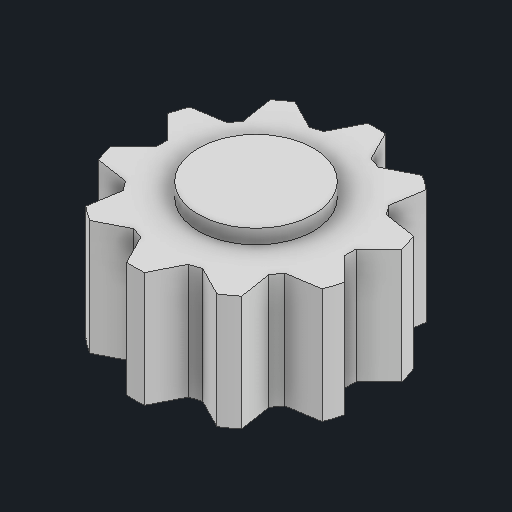
# Autodesk Inventor part: motor_gear
Saved by Autodesk Inventor 2026.1 (Build 301233020, 233B)
## iProperties
Created: 2025-11-26
Part Number: motor_gear
Material: Generico
Document SubType Name: Modeling
Designer: maxbu
Density: 1 g/cm^3
Appearance: Default
Author: maxbu
Autodesk Inventor part; units mm, degrees
ref_plane "YZ Plane" through (0, 0, 0) normal (1, 0, 0) x (0, 1, 0)
ref_plane "XZ Plane" through (0, 0, 0) normal (0, 1, 0) x (-1, 0, 0)
ref_plane "XY Plane" through (0, 0, 0) normal (0, 0, 1) x (1, 0, 0)
sketch "Sketch6" plane through (0, 0, 0) normal (0, 1, 0) x (-1, 0, 0)
  circle A0 centre (0, 0) radius 4.2
  dimension "d37" = 8.4
  constraints: 1 centre point, 1 coincident
  measures "d37" diameter of A0
extrude "Extrusion5" add sketch "Sketch6" along normal blind 4
sketch "Sketch7" plane through (0, 0, 0) normal (0, 1, 0) x (-1, 0, 0)
  circle A0 centre (0, 0) radius 4.2 projected
  line L0 (-5.88, 0) -> (5.88, 0) projected
  line L1 (4.0792, 1) -> (3.2792, 0.2)
  line L2 (3.2792, -0.2) -> (4.0792, -1)
  line L3 (3.2792, 0.2) -> (3.2792, -0.2)
  dimension "d44" = 45
  dimension "d45" = 1
  dimension "d46" = 0.8
  dimension "d47" = 0.4
  constraints: 6 end point, 2 point on circle, 1 vertical, 1 other
  measures "d44" angle of L0 L1
  measures "d45" distance from line of L2.end L0
  measures "d46" horizontal distance of L2.end L2.start
  measures "d47" distance of L2.start L1.end
extrude "Extrusion6" cut sketch "Sketch7" along normal through all contours L0 L3 L1 A0 | A0 L2 L3 L0 picked at (3.8349, 0.6234) picked at (3.8349, -0.6234)
pattern_circular "Circular Pattern1" count 10 over 360 about axis through (0, -10, 0) along (0, 1, 0) of "Extrusion6"
sketch "Sketch8" plane through (0, 4, 0) normal (0, 1, 0) x (1, 0, 0)
  circle A0 centre (0, 0) radius 2
  dimension "d53" = 4
  constraints: 1 centre point, 1 coincident
  measures "d53" diameter of A0
extrude "Extrusion7" add sketch "Sketch8" along normal blind 0.5
body "Solid2"
